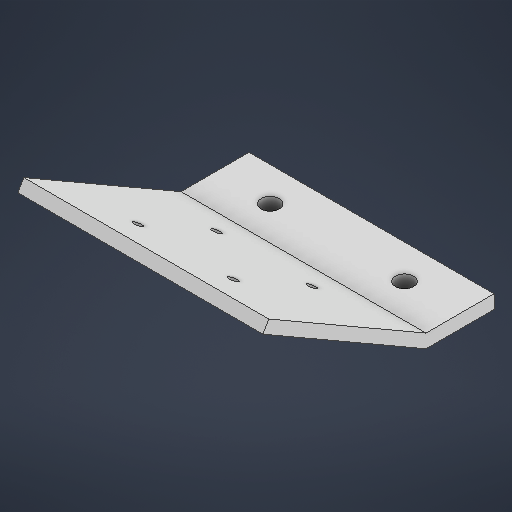
# Autodesk Inventor part: Soporte de Camara
Saved by Autodesk Inventor 2026.1 (Build 301233020, 233B)
## iProperties
Created: 2026-08-16
Part Number: Soporte de Camara
Material: Genérico
Document SubType Name: Modeling
Designer: allan
Density: 1 g/cm^3
Appearance: Valor por defecto
Author: allan
Autodesk Inventor part; units mm, degrees
ref_plane "YZ Plane" through (0, 0, 0) normal (1, 0, 0) x (0, 1, 0)
ref_plane "XZ Plane" through (0, 0, 0) normal (0, 1, 0) x (-1, 0, 0)
ref_plane "XY Plane" through (0, 0, 0) normal (0, 0, 1) x (1, 0, 0)
sketch "Boceto1" plane through (0, 0, 0) normal (0, 1, 0) x (-1, 0, 0)
  line L0 (27, 7.5) -> (-27, 7.5)
  line L1 (-27, 7.5) -> (-27, -7.5)
  line L2 (-27, -7.5) -> (27, -7.5)
  line L3 (27, -7.5) -> (27, 7.5)
  line L4 (27, 7.5) -> (-27, -7.5) construction
  line L5 (-27, 7.5) -> (27, -7.5) construction
  line L6 (27, 0) -> (14.84, 0)
  line L7 (-27, 0) -> (-14.75, 0)
  circle A0 centre (14.84, 0) radius 2
  circle A1 centre (-14.75, 0) radius 2
  point P0 (0, 0)
  dimension "d0" = 54
  dimension "d1" = 15
  dimension "d2" = 12.16
  dimension "d3" = 12.25
  dimension "d4" = 4
  dimension "d5" = 4
  constraints: 16 end point, 4 midpoint, 3 horizontal, 2 centre point, 2 coincident, 2 parallel, 1 perpendicular
  measures "d0" distance of L2.end L1.end
  measures "d1" distance of L1.end L0.end
  measures "d2" distance of L6.start L6.end
  measures "d3" distance of L7.start L7.end
  measures "d4" diameter of A0
  measures "d5" diameter of A1
extrude "Extrusión1" add sketch "Boceto1" along normal blind 3
sketch "Boceto6" plane through (27, 0, 7.5) normal (1, 0, 0) x (0, 0, -1)
  line L0 (0, 3) -> (-34.641, 23)
  line L1 (0, 3) -> (40, 3) construction
  line L2 (0, 0) -> (-35.9401, 20.75)
  line L3 (-35.9401, 20.75) -> (-34.641, 23)
  line L4 (0, 0) -> (0, 3)
  point P0 (7.5, 0)
  dimension "d39" = 40
  dimension "d40" = 150
  constraints: 10 end point, 1 equal length, 1 horizontal, 1 perpendicular, 1 vertical
  measures "d39" distance of L0.start L0.end
  measures "d40" angle of L1 L0
extrude "Extrusión6" add sketch "Boceto6" against normal blind 54
sketch "Boceto7" plane through (-27, 0, 7.5) normal (0, -0.866, 0.5) x (1, 0, 0)
  line L0 (14.5, 33.5) -> (39.5, 33.5)
  line L1 (39.5, 33.5) -> (39.5, 9.5)
  line L2 (39.5, 9.5) -> (14.5, 9.5)
  line L3 (14.5, 9.5) -> (14.5, 33.5)
  line L4 (14.5, 33.5) -> (39.5, 9.5) construction
  line L5 (39.5, 33.5) -> (14.5, 9.5) construction
  point P0 (27, -6.4952)
  point P1 (27, 21.5)
  dimension "d44" = 25
  dimension "d45" = 24
  constraints: 12 end point, 2 midpoint, 2 parallel, 1 horizontal, 1 perpendicular
  measures "d44" distance of L1.end L2.end
  measures "d45" distance of L0.end L1.end
extrude "Extrusión7" add sketch "Boceto7" along normal blind 1
sketch "Boceto8" plane through (-27, -0.866, 8) normal (0, -0.866, 0.5) x (1, 0, 0)
  point P0 (27, -6.4952)
sketch "Boceto9" plane through (-27, -0.866, 8) normal (0, -0.866, 0.5) x (1, 0, 0)
  line L0 (14.5, 9.5) -> (14.5, 33.5) projected
  line L1 (14.5, 33.5) -> (14.5, 31.5)
  line L2 (14.5, 31.5) -> (16.5, 31.5)
  line L3 (39.5, 33.5) -> (39.5, 9.5) projected
  line L4 (39.5, 31.5) -> (39.5, 33.5)
  line L5 (39.5, 31.5) -> (37.5, 31.5)
  line L6 (14.5, 9.5) -> (14.5, 11.5)
  line L7 (14.5, 11.5) -> (16.5, 11.5)
  line L8 (39.5, 9.5) -> (39.5, 11.5)
  line L9 (39.5, 9.5) -> (39.5, 11.5)
  line L10 (37.5, 11.5) -> (39.5, 11.5)
  circle A0 centre (16.5, 31.5) radius 1
  circle A1 centre (37.5, 31.5) radius 1
  circle A2 centre (16.5, 11.5) radius 1
  circle A3 centre (37.5, 11.5) radius 1
  point P0 (27, -6.4952)
  dimension "d48" = 2
  dimension "d49" = 2
  dimension "d50" = 2
  dimension "d51" = 2
  dimension "d52" = 2
  dimension "d53" = 2
  dimension "d54" = 2
  dimension "d55" = 2
  dimension "d56" = 2
  constraints: 18 end point, 4 centre point, 4 coincident, 4 point on line, 3 perpendicular, 2 collinear, 1 horizontal
  measures "d48" distance of L0.end L1.end
  measures "d49" distance of L1.end L2.end
  measures "d50" distance of L4.start L3.start
  measures "d51" distance of L4.start L5.end
  measures "d52" distance of L0.start L6.end
  measures "d53" diameter of A0
  measures "d54" diameter of A1
  measures "d55" diameter of A2
  measures "d56" diameter of A3
extrude "Extrusión8" cut sketch "Boceto9" against normal blind 10
